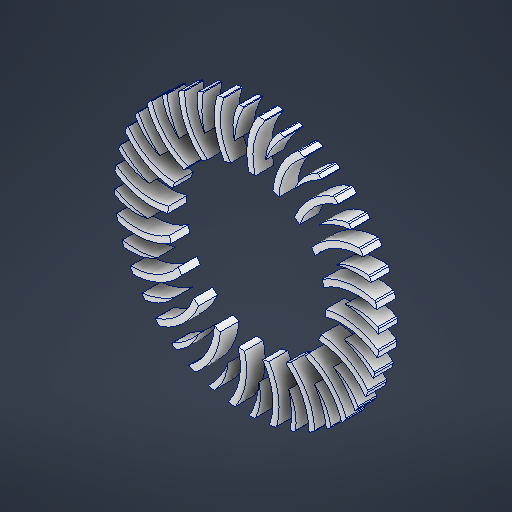
# Autodesk Inventor part: cooling fins
Saved by Autodesk Inventor 2027 (Build 310192060, 192F)
## iProperties
Created: 2026-06-30
Part Number: cooling fins
Material: Aluminum 6061
Document SubType Name: Modeling
Designer: ElieH
Density: 2.7 g/cm^3
Appearance: Aluminum - Flat
Author: ElieH
Autodesk Inventor part; units mm, degrees
ref_plane "YZ Plane" through (0, 0, 0) normal (1, 0, 0) x (0, 1, 0)
ref_plane "XZ Plane" through (0, 0, 0) normal (0, 1, 0) x (-1, 0, 0)
ref_plane "XY Plane" through (0, 0, 0) normal (0, 0, 1) x (1, 0, 0)
sketch "Sketch1" plane through (0, 0, 0) normal (0, 0, 1) x (1, 0, 0)
  circle A0 centre (-0.4718, -0.0423) radius 145.0085
  arc A1 (97.2121, 102.2714) -> (93.1342, 105.9987) centre (0.1506, 0.1757) ccw
  arc A2 (93.1342, 105.9987) -> (91.3573, 106.326) centre (91.9719, 104.6759) ccw
  arc A3 (91.3573, 106.326) -> (84.0675, 103.1281) centre (115.8041, 40.6903) ccw
  arc A4 (91.3573, 106.326) -> (50.7902, 66.7457) centre (115.8041, 40.6903) ccw
  arc A5 (79.6447, 115.6743) -> (50.85, 92.7581) centre (115.8041, 40.6903) ccw
  arc A6 (74.2845, 118.9255) -> (50.85, 92.7581) centre (97.6239, 74.4463) ccw
  arc A7 (76.0515, 118.8497) -> (74.2845, 118.9255) centre (75.1027, 117.3662) ccw
  arc A8 (79.7021, 116.4341) -> (76.0515, 118.8497) centre (0.1506, 0.1757) ccw
  arc A9 (79.6447, 115.6743) -> (79.7021, 116.4341) centre (79.4535, 116.0708) ccw
  arc A10 (97.4056, 102.0871) -> (97.2121, 102.2714) centre (0.1506, 0.1757) ccw
  arc A11 (97.2305, 101.3477) -> (97.0044, 101.278) centre (115.8041, 40.6903) ccw
  arc A12 (97.2305, 101.3477) -> (97.4056, 102.0871) centre (97.1016, 101.7686) ccw
  arc A13 (97.0044, 101.278) -> (56.1595, 62.2961) centre (115.8041, 40.6903) ccw
  arc A14 (56.1595, 62.2961) -> (50.7902, 66.7457) centre (0.1506, 0.1757) ccw
  arc A15 (33.8626, 136.2038) -> (19.6612, 104.0754) centre (69.8045, 101.1138) ccw
  arc A16 (39.9651, 134.768) -> (19.6612, 104.0754) centre (97.526, 74.6279) ccw
  arc A17 (39.7849, 135.5084) -> (35.5665, 136.6777) centre (0.0527, 0.3573) ccw
  arc A18 (35.5665, 136.6777) -> (33.8626, 136.2038) centre (35.1226, 134.9737) ccw
  arc A19 (39.9651, 134.768) -> (39.7849, 135.5084) centre (39.6607, 135.0861) ccw
  arc A20 (53.9933, 129.4967) -> (27.6426, 79.3177) centre (97.526, 74.6279) ccw
  arc A21 (55.7844, 129.7345) -> (53.9933, 129.4967) centre (55.0877, 128.1173) ccw
  arc A22 (60.8144, 127.4497) -> (55.7844, 129.7345) centre (0.0527, 0.3573) ccw
  arc A23 (61.0554, 127.3343) -> (60.8144, 127.4497) centre (0.0527, 0.3573) ccw
  arc A24 (61.1174, 126.577) -> (61.0554, 127.3343) centre (60.8647, 126.9375) ccw
  arc A25 (61.1174, 126.577) -> (60.9238, 126.4408) centre (97.526, 74.6279) ccw
  arc A26 (60.9238, 126.4408) -> (34.1241, 76.7451) centre (97.526, 74.6279) ccw
  arc A27 (34.1241, 76.7451) -> (27.6426, 79.3177) centre (0.0527, 0.3573) ccw
  arc A28 (-9.9202, 140.1453) -> (-13.4984, 105.201) centre (35.1059, 117.8794) ccw
  arc A29 (-3.6727, 140.6656) -> (-13.4984, 105.201) centre (69.6553, 101.2563) ccw
  arc A30 (-4.0729, 141.3141) -> (-8.4461, 141.1225) centre (-0.0964, 0.4998) ccw
  arc A31 (-8.4461, 141.1225) -> (-9.9202, 140.1453) centre (-8.3418, 139.3648) ccw
  arc A32 (-3.6727, 140.6656) -> (-4.0729, 141.3141) centre (-4.0605, 140.874) ccw
  arc A33 (11.2978, 139.9872) -> (1.743, 84.1214) centre (69.6553, 101.2563) ccw
  arc A34 (12.9277, 140.7668) -> (11.2978, 139.9872) centre (12.7649, 139.0135) ccw
  arc A35 (18.4176, 140.1483) -> (12.9277, 140.7668) centre (-0.0964, 0.4998) ccw
  arc A36 (18.6825, 140.1129) -> (18.4176, 140.1483) centre (-0.0964, 0.4998) ccw
  arc A37 (18.9755, 139.4119) -> (18.6825, 140.1129) centre (18.6238, 139.6766) ccw
  arc A38 (18.9755, 139.4119) -> (18.8335, 139.2225) centre (69.6553, 101.2563) ccw
  arc A39 (18.8335, 139.2225) -> (8.7022, 83.6775) centre (69.6553, 101.2563) ccw
  arc A40 (8.7022, 83.6775) -> (1.743, 84.1214) centre (-0.0964, 0.4998) ccw
  arc A41 (-52.7781, 130.3643) -> (-45.3828, 96.0246) centre (-3.0752, 123.102) ccw
  arc A42 (-46.9972, 132.7897) -> (-45.3828, 96.0246) centre (34.92, 117.9688) ccw
  arc A43 (-47.5782, 133.2828) -> (-51.6782, 131.7492) centre (-0.2823, 0.5893) ccw
  arc A44 (-51.6782, 131.7492) -> (-52.7781, 130.3643) centre (-51.0357, 130.1097) ccw
  arc A45 (-46.9972, 132.7897) -> (-47.5782, 133.2828) centre (-47.4304, 132.8681) ccw
  arc A46 (-32.5498, 136.7707) -> (-24.3734, 80.6865) centre (34.92, 117.9688) ccw
  arc A47 (-31.2405, 138.0158) -> (-32.5498, 136.7707) centre (-30.8535, 136.298) ccw
  arc A48 (-25.8282, 139.124) -> (-31.2405, 138.0158) centre (-0.2823, 0.5893) ccw
  arc A49 (-25.5654, 139.1722) -> (-25.8282, 139.124) centre (-0.2823, 0.5893) ccw
  arc A50 (-25.0701, 138.596) -> (-25.5654, 139.1722) centre (-25.4863, 138.7392) ccw
  arc A51 (-25.0701, 138.596) -> (-25.1466, 138.3721) centre (34.92, 117.9688) ccw
  arc A52 (-25.1466, 138.3721) -> (-17.6176, 82.4149) centre (34.92, 117.9688) ccw
  arc A53 (-17.6176, 82.4149) -> (-24.3734, 80.6865) centre (-0.2823, 0.5893) ccw
  arc A54 (-90.5159, 107.8182) -> (-72.871, 77.4444) centre (-41.0015, 116.2704) ccw
  arc A55 (-85.7675, 111.9113) -> (-72.871, 77.4444) centre (-3.2796, 123.1296) ccw
  arc A56 (-86.4724, 112.2007) -> (-89.8978, 109.4752) centre (-0.4868, 0.6169) ccw
  arc A57 (-89.8978, 109.4752) -> (-90.5159, 107.8182) centre (-88.7802, 108.1145) ccw
  arc A58 (-85.7675, 111.9113) -> (-86.4724, 112.2007) centre (-86.2037, 111.852) ccw
  arc A59 (-73.2573, 120.1619) -> (-48.1502, 69.3494) centre (-3.2796, 123.1296) ccw
  arc A60 (-72.3969, 121.7507) -> (-73.2573, 120.1619) centre (-71.498, 120.2365) ccw
  arc A61 (-67.5919, 124.4772) -> (-72.3969, 121.7507) centre (-0.4868, 0.6169) ccw
  arc A62 (-67.3569, 124.6042) -> (-67.5919, 124.4772) centre (-0.4868, 0.6169) ccw
  arc A63 (-66.7077, 124.2093) -> (-67.3569, 124.6042) centre (-67.1479, 124.2168) ccw
  arc A64 (-66.7077, 124.2093) -> (-66.7113, 123.9727) centre (-3.2796, 123.1296) ccw
  arc A65 (-66.7113, 123.9727) -> (-42.2592, 73.0808) centre (-3.2796, 123.1296) ccw
  arc A66 (-42.2592, 73.0808) -> (-48.1502, 69.3494) centre (-0.4868, 0.6169) ccw
  arc A67 (-119.4396, 74.714) -> (-93.2723, 51.2794) centre (-74.9604, 98.0533) ccw
  arc A68 (-116.1884, 80.0741) -> (-93.2723, 51.2794) centre (-41.2044, 116.2335) ccw
  arc A69 (-116.9482, 80.1315) -> (-119.3638, 76.4809) centre (-0.6898, 0.58) ccw
  arc A70 (-119.3638, 76.4809) -> (-119.4396, 74.714) centre (-117.8803, 75.5321) ccw
  arc A71 (-116.1884, 80.0741) -> (-116.9482, 80.1315) centre (-116.5849, 79.8829) ccw
  arc A72 (-106.8401, 91.7867) -> (-67.2598, 51.2196) centre (-41.2044, 116.2335) ccw
  arc A73 (-106.5128, 93.5636) -> (-106.8401, 91.7867) centre (-105.19, 92.4014) ccw
  arc A74 (-102.7855, 97.6415) -> (-106.5128, 93.5636) centre (-0.6898, 0.58) ccw
  arc A75 (-102.6012, 97.835) -> (-102.7855, 97.6415) centre (-0.6898, 0.58) ccw
  arc A76 (-101.8618, 97.6599) -> (-102.6012, 97.835) centre (-102.2827, 97.531) ccw
  arc A77 (-101.8618, 97.6599) -> (-101.7921, 97.4338) centre (-41.2044, 116.2335) ccw
  arc A78 (-101.7921, 97.4338) -> (-62.8102, 56.5889) centre (-41.2044, 116.2335) ccw
  arc A79 (-62.8102, 56.5889) -> (-67.2598, 51.2196) centre (-0.6898, 0.58) ccw
  arc A80 (-136.7179, 34.292) -> (-104.5896, 20.0906) centre (-101.6279, 70.2339) ccw
  arc A81 (-135.2822, 40.3945) -> (-104.5896, 20.0906) centre (-75.142, 97.9555) ccw
  arc A82 (-136.0225, 40.2143) -> (-137.1918, 35.9959) centre (-0.8714, 0.4821) ccw
  arc A83 (-137.1918, 35.9959) -> (-136.7179, 34.292) centre (-135.4878, 35.552) ccw
  arc A84 (-135.2822, 40.3945) -> (-136.0225, 40.2143) centre (-135.6002, 40.0901) ccw
  arc A85 (-130.0108, 54.4227) -> (-79.8318, 28.072) centre (-75.142, 97.9555) ccw
  arc A86 (-130.2486, 56.2138) -> (-130.0108, 54.4227) centre (-128.6314, 55.5171) ccw
  arc A87 (-127.9638, 61.2438) -> (-130.2486, 56.2138) centre (-0.8714, 0.4821) ccw
  arc A88 (-127.8484, 61.4848) -> (-127.9638, 61.2438) centre (-0.8714, 0.4821) ccw
  arc A89 (-127.0911, 61.5468) -> (-127.8484, 61.4848) centre (-127.4516, 61.2941) ccw
  arc A90 (-127.0911, 61.5468) -> (-126.9549, 61.3533) centre (-75.142, 97.9555) ccw
  arc A91 (-126.9549, 61.3533) -> (-77.2592, 34.5535) centre (-75.142, 97.9555) ccw
  arc A92 (-77.2592, 34.5535) -> (-79.8318, 28.072) centre (-0.8714, 0.4821) ccw
  arc A93 (-140.6594, -9.4908) -> (-105.7151, -13.069) centre (-118.3935, 35.5354) ccw
  arc A94 (-141.1797, -3.2433) -> (-105.7151, -13.069) centre (-101.7704, 70.0847) ccw
  arc A95 (-141.8282, -3.6435) -> (-141.6367, -8.0167) centre (-1.0139, 0.333) ccw
  arc A96 (-141.6367, -8.0167) -> (-140.6594, -9.4908) centre (-139.8789, -7.9123) ccw
  arc A97 (-141.1797, -3.2433) -> (-141.8282, -3.6435) centre (-141.3881, -3.6311) ccw
  arc A98 (-140.5013, 11.7272) -> (-84.6355, 2.1724) centre (-101.7704, 70.0847) ccw
  arc A99 (-141.281, 13.3572) -> (-140.5013, 11.7272) centre (-139.5276, 13.1944) ccw
  arc A100 (-140.6624, 18.847) -> (-141.281, 13.3572) centre (-1.0139, 0.333) ccw
  arc A101 (-140.627, 19.1119) -> (-140.6624, 18.847) centre (-1.0139, 0.333) ccw
  arc A102 (-139.926, 19.4049) -> (-140.627, 19.1119) centre (-140.1907, 19.0532) ccw
  arc A103 (-139.926, 19.4049) -> (-139.7366, 19.2629) centre (-101.7704, 70.0847) ccw
  arc A104 (-139.7366, 19.2629) -> (-84.1916, 9.1316) centre (-101.7704, 70.0847) ccw
  arc A105 (-84.1916, 9.1316) -> (-84.6355, 2.1724) centre (-1.0139, 0.333) ccw
  arc A106 (-130.8784, -52.3487) -> (-96.5387, -44.9534) centre (-123.6161, -2.6458) ccw
  arc A107 (-133.3038, -46.5678) -> (-96.5387, -44.9534) centre (-118.483, 35.3494) ccw
  arc A108 (-133.7969, -47.1488) -> (-132.2633, -51.2488) centre (-1.1034, 0.1471) ccw
  arc A109 (-132.2633, -51.2488) -> (-130.8784, -52.3487) centre (-130.6238, -50.6063) ccw
  arc A110 (-133.3038, -46.5678) -> (-133.7969, -47.1488) centre (-133.3822, -47.001) ccw
  arc A111 (-137.2848, -32.1204) -> (-81.2006, -23.944) centre (-118.483, 35.3494) ccw
  arc A112 (-138.5299, -30.8111) -> (-137.2848, -32.1204) centre (-136.8121, -30.4241) ccw
  arc A113 (-139.6381, -25.3988) -> (-138.5299, -30.8111) centre (-1.1034, 0.1471) ccw
  arc A114 (-139.6863, -25.1359) -> (-139.6381, -25.3988) centre (-1.1034, 0.1471) ccw
  arc A115 (-139.1101, -24.6406) -> (-139.6863, -25.1359) centre (-139.2533, -25.0569) ccw
  arc A116 (-139.1101, -24.6406) -> (-138.8862, -24.7172) centre (-118.483, 35.3494) ccw
  arc A117 (-138.8862, -24.7172) -> (-82.929, -17.1882) centre (-118.483, 35.3494) ccw
  arc A118 (-82.929, -17.1882) -> (-81.2006, -23.944) centre (-1.1034, 0.1471) ccw
  arc A119 (-108.3323, -90.0865) -> (-77.9585, -72.4416) centre (-116.7845, -40.572) ccw
  arc A120 (-112.4254, -85.3381) -> (-77.9585, -72.4416) centre (-123.6437, -2.8502) ccw
  arc A121 (-112.7148, -86.043) -> (-109.9893, -89.4684) centre (-1.131, -0.0574) ccw
  arc A122 (-109.9893, -89.4684) -> (-108.3323, -90.0865) centre (-108.6286, -88.3508) ccw
  arc A123 (-112.4254, -85.3381) -> (-112.7148, -86.043) centre (-112.3661, -85.7743) ccw
  arc A124 (-120.676, -72.8279) -> (-69.8635, -47.7208) centre (-123.6437, -2.8502) ccw
  arc A125 (-122.2648, -71.9675) -> (-120.676, -72.8279) centre (-120.7506, -71.0686) ccw
  arc A126 (-124.9913, -67.1625) -> (-122.2648, -71.9675) centre (-1.131, -0.0574) ccw
  arc A127 (-125.1183, -66.9275) -> (-124.9913, -67.1625) centre (-1.131, -0.0574) ccw
  arc A128 (-124.7234, -66.2783) -> (-125.1183, -66.9275) centre (-124.7309, -66.7185) ccw
  arc A129 (-124.7234, -66.2783) -> (-124.4868, -66.2819) centre (-123.6437, -2.8502) ccw
  arc A130 (-124.4868, -66.2819) -> (-73.5949, -41.8298) centre (-123.6437, -2.8502) ccw
  arc A131 (-73.5949, -41.8298) -> (-69.8635, -47.7208) centre (-1.131, -0.0574) ccw
  arc A132 (-75.2281, -119.0102) -> (-51.7935, -92.8428) centre (-98.5674, -74.531) ccw
  arc A133 (-80.5882, -115.759) -> (-51.7935, -92.8428) centre (-116.7476, -40.775) ccw
  arc A134 (-80.6456, -116.5188) -> (-76.995, -118.9344) centre (-1.0941, -0.2604) ccw
  arc A135 (-76.995, -118.9344) -> (-75.2281, -119.0102) centre (-76.0462, -117.4509) ccw
  arc A136 (-80.5882, -115.759) -> (-80.6456, -116.5188) centre (-80.397, -116.1555) ccw
  arc A137 (-92.3008, -106.4107) -> (-51.7337, -66.8304) centre (-116.7476, -40.775) ccw
  arc A138 (-94.0778, -106.0833) -> (-92.3008, -106.4107) centre (-92.9155, -104.7606) ccw
  arc A139 (-98.1556, -102.3561) -> (-94.0778, -106.0833) centre (-1.0941, -0.2604) ccw
  arc A140 (-98.3491, -102.1718) -> (-98.1556, -102.3561) centre (-1.0941, -0.2604) ccw
  arc A141 (-98.174, -101.4324) -> (-98.3491, -102.1718) centre (-98.0451, -101.8533) ccw
  arc A142 (-98.174, -101.4324) -> (-97.9479, -101.3627) centre (-116.7476, -40.775) ccw
  arc A143 (-97.9479, -101.3627) -> (-57.103, -62.3808) centre (-116.7476, -40.775) ccw
  arc A144 (-57.103, -62.3808) -> (-51.7337, -66.8304) centre (-1.0941, -0.2604) ccw
  arc A145 (-34.8061, -136.2885) -> (-20.6047, -104.1601) centre (-70.748, -101.1985) ccw
  arc A146 (-40.9086, -134.8527) -> (-20.6047, -104.1601) centre (-98.4696, -74.7126) ccw
  arc A147 (-40.7284, -135.5931) -> (-36.51, -136.7624) centre (-0.9963, -0.442) ccw
  arc A148 (-36.51, -136.7624) -> (-34.8061, -136.2885) centre (-36.0661, -135.0583) ccw
  arc A149 (-40.9086, -134.8527) -> (-40.7284, -135.5931) centre (-40.6042, -135.1708) ccw
  arc A150 (-54.9368, -129.5814) -> (-28.5862, -79.4024) centre (-98.4696, -74.7126) ccw
  arc A151 (-56.7279, -129.8192) -> (-54.9368, -129.5814) centre (-56.0312, -128.202) ccw
  arc A152 (-61.7579, -127.5344) -> (-56.7279, -129.8192) centre (-0.9963, -0.442) ccw
  arc A153 (-61.9989, -127.419) -> (-61.7579, -127.5344) centre (-0.9963, -0.442) ccw
  arc A154 (-62.0609, -126.6617) -> (-61.9989, -127.419) centre (-61.8083, -127.0222) ccw
  arc A155 (-62.0609, -126.6617) -> (-61.8674, -126.5255) centre (-98.4696, -74.7126) ccw
  arc A156 (-61.8674, -126.5255) -> (-35.0676, -76.8298) centre (-98.4696, -74.7126) ccw
  arc A157 (-35.0676, -76.8298) -> (-28.5862, -79.4024) centre (-0.9963, -0.442) ccw
  arc A158 (8.9767, -140.23) -> (12.5549, -105.2857) centre (-36.0495, -117.9641) ccw
  arc A159 (2.7292, -140.7503) -> (12.5549, -105.2857) centre (-70.5988, -101.341) ccw
  arc A160 (3.1294, -141.3988) -> (7.5026, -141.2072) centre (-0.8471, -0.5845) ccw
  arc A161 (7.5026, -141.2072) -> (8.9767, -140.23) centre (7.3982, -139.4495) ccw
  arc A162 (2.7292, -140.7503) -> (3.1294, -141.3988) centre (3.117, -140.9587) ccw
  arc A163 (-12.2413, -140.0719) -> (-2.6865, -84.2061) centre (-70.5988, -101.341) ccw
  arc A164 (-13.8713, -140.8515) -> (-12.2413, -140.0719) centre (-13.7085, -139.0982) ccw
  arc A165 (-19.3611, -140.233) -> (-13.8713, -140.8515) centre (-0.8471, -0.5845) ccw
  arc A166 (-19.626, -140.1976) -> (-19.3611, -140.233) centre (-0.8471, -0.5845) ccw
  arc A167 (-19.919, -139.4966) -> (-19.626, -140.1976) centre (-19.5673, -139.7613) ccw
  arc A168 (-19.919, -139.4966) -> (-19.777, -139.3072) centre (-70.5988, -101.341) ccw
  arc A169 (-19.777, -139.3072) -> (-9.6457, -83.7622) centre (-70.5988, -101.341) ccw
  arc A170 (-9.6457, -83.7622) -> (-2.6865, -84.2061) centre (-0.8471, -0.5845) ccw
  arc A171 (51.8346, -130.449) -> (44.4393, -96.1092) centre (2.1317, -123.1867) ccw
  arc A172 (46.0537, -132.8744) -> (44.4393, -96.1092) centre (-35.8636, -118.0535) ccw
  arc A173 (46.6347, -133.3675) -> (50.7347, -131.8339) centre (-0.6612, -0.674) ccw
  arc A174 (50.7347, -131.8339) -> (51.8346, -130.449) centre (50.0922, -130.1944) ccw
  arc A175 (46.0537, -132.8744) -> (46.6347, -133.3675) centre (46.4869, -132.9528) ccw
  arc A176 (31.6063, -136.8554) -> (23.4299, -80.7712) centre (-35.8636, -118.0535) ccw
  arc A177 (30.297, -138.1005) -> (31.6063, -136.8554) centre (29.91, -136.3827) ccw
  arc A178 (24.8847, -139.2087) -> (30.297, -138.1005) centre (-0.6612, -0.674) ccw
  arc A179 (24.6218, -139.2569) -> (24.8847, -139.2087) centre (-0.6612, -0.674) ccw
  arc A180 (24.1265, -138.6807) -> (24.6218, -139.2569) centre (24.5428, -138.8239) ccw
  arc A181 (24.1265, -138.6807) -> (24.2031, -138.4568) centre (-35.8636, -118.0535) ccw
  arc A182 (24.2031, -138.4568) -> (16.6741, -82.4996) centre (-35.8636, -118.0535) ccw
  arc A183 (16.6741, -82.4996) -> (23.4299, -80.7712) centre (-0.6612, -0.674) ccw
  arc A184 (89.5724, -107.9029) -> (71.9275, -77.5291) centre (40.0579, -116.3551) ccw
  arc A185 (84.824, -111.996) -> (71.9275, -77.5291) centre (2.3361, -123.2143) ccw
  arc A186 (85.5289, -112.2854) -> (88.9543, -109.5599) centre (-0.4567, -0.7016) ccw
  arc A187 (88.9543, -109.5599) -> (89.5724, -107.9029) centre (87.8366, -108.1992) ccw
  arc A188 (84.824, -111.996) -> (85.5289, -112.2854) centre (85.2602, -111.9367) ccw
  arc A189 (72.3138, -120.2466) -> (47.2067, -69.434) centre (2.3361, -123.2143) ccw
  arc A190 (71.4534, -121.8354) -> (72.3138, -120.2466) centre (70.5545, -120.3212) ccw
  arc A191 (66.6484, -124.5619) -> (71.4534, -121.8354) centre (-0.4567, -0.7016) ccw
  arc A192 (66.4133, -124.6889) -> (66.6484, -124.5619) centre (-0.4567, -0.7016) ccw
  arc A193 (65.7642, -124.294) -> (66.4133, -124.6889) centre (66.2044, -124.3015) ccw
  arc A194 (65.7642, -124.294) -> (65.7678, -124.0573) centre (2.3361, -123.2143) ccw
  arc A195 (65.7678, -124.0573) -> (41.3156, -73.1655) centre (2.3361, -123.2143) ccw
  arc A196 (41.3156, -73.1655) -> (47.2067, -69.434) centre (-0.4567, -0.7016) ccw
  arc A197 (118.4961, -74.7987) -> (92.3287, -51.3641) centre (74.0169, -98.138) ccw
  arc A198 (115.2449, -80.1588) -> (92.3287, -51.3641) centre (40.2609, -116.3182) ccw
  arc A199 (116.0047, -80.2162) -> (118.4203, -76.5656) centre (-0.2538, -0.6647) ccw
  arc A200 (118.4203, -76.5656) -> (118.4961, -74.7987) centre (116.9368, -75.6168) ccw
  arc A201 (115.2449, -80.1588) -> (116.0047, -80.2162) centre (115.6414, -79.9676) ccw
  arc A202 (105.8966, -91.8714) -> (66.3163, -51.3043) centre (40.2609, -116.3182) ccw
  arc A203 (105.5692, -93.6483) -> (105.8966, -91.8714) centre (104.2465, -92.486) ccw
  arc A204 (101.842, -97.7262) -> (105.5692, -93.6483) centre (-0.2538, -0.6647) ccw
  arc A205 (101.6577, -97.9197) -> (101.842, -97.7262) centre (-0.2538, -0.6647) ccw
  arc A206 (100.9183, -97.7446) -> (101.6577, -97.9197) centre (101.3392, -97.6157) ccw
  arc A207 (100.9183, -97.7446) -> (100.8486, -97.5185) centre (40.2609, -116.3182) ccw
  arc A208 (100.8486, -97.5185) -> (61.8667, -56.6736) centre (40.2609, -116.3182) ccw
  arc A209 (61.8667, -56.6736) -> (66.3163, -51.3043) centre (-0.2538, -0.6647) ccw
  arc A210 (135.7744, -34.3767) -> (103.646, -20.1753) centre (100.6844, -70.3186) ccw
  arc A211 (134.3386, -40.4792) -> (103.646, -20.1753) centre (74.1985, -98.0402) ccw
  arc A212 (135.079, -40.299) -> (136.2482, -36.0806) centre (-0.0721, -0.5668) ccw
  arc A213 (136.2482, -36.0806) -> (135.7744, -34.3767) centre (134.5442, -35.6367) ccw
  arc A214 (134.3386, -40.4792) -> (135.079, -40.299) centre (134.6567, -40.1748) ccw
  arc A215 (129.0673, -54.5074) -> (78.8883, -28.1567) centre (74.1985, -98.0402) ccw
  arc A216 (129.3051, -56.2985) -> (129.0673, -54.5074) centre (127.6879, -55.6018) ccw
  arc A217 (127.0203, -61.3285) -> (129.3051, -56.2985) centre (-0.0721, -0.5668) ccw
  arc A218 (126.9048, -61.5695) -> (127.0203, -61.3285) centre (-0.0721, -0.5668) ccw
  arc A219 (126.1475, -61.6315) -> (126.9048, -61.5695) centre (126.508, -61.3788) ccw
  arc A220 (126.1475, -61.6315) -> (126.0114, -61.438) centre (74.1985, -98.0402) ccw
  arc A221 (126.0114, -61.438) -> (76.3157, -34.6382) centre (74.1985, -98.0402) ccw
  arc A222 (76.3157, -34.6382) -> (78.8883, -28.1567) centre (-0.0721, -0.5668) ccw
  arc A223 (139.7159, 9.4061) -> (104.7716, 12.9843) centre (117.45, -35.6201) ccw
  arc A224 (140.2362, 3.1586) -> (104.7716, 12.9843) centre (100.8269, -70.1694) ccw
  arc A225 (140.8847, 3.5588) -> (140.6931, 7.932) centre (0.0704, -0.4177) ccw
  arc A226 (140.6931, 7.932) -> (139.7159, 9.4061) centre (138.9354, 7.8276) ccw
  arc A227 (140.2362, 3.1586) -> (140.8847, 3.5588) centre (140.4446, 3.5464) ccw
  arc A228 (139.5578, -11.8119) -> (83.692, -2.2571) centre (100.8269, -70.1694) ccw
  arc A229 (140.3374, -13.4419) -> (139.5578, -11.8119) centre (138.5841, -13.2791) ccw
  arc A230 (139.7189, -18.9317) -> (140.3374, -13.4419) centre (0.0704, -0.4177) ccw
  arc A231 (139.6835, -19.1966) -> (139.7189, -18.9317) centre (0.0704, -0.4177) ccw
  arc A232 (138.9825, -19.4896) -> (139.6835, -19.1966) centre (139.2472, -19.1379) ccw
  arc A233 (138.9825, -19.4896) -> (138.7931, -19.3476) centre (100.8269, -70.1694) ccw
  arc A234 (138.7931, -19.3476) -> (83.2481, -9.2163) centre (100.8269, -70.1694) ccw
  arc A235 (83.2481, -9.2163) -> (83.692, -2.2571) centre (0.0704, -0.4177) ccw
  arc A236 (129.9349, 52.264) -> (95.5951, 44.8687) centre (122.6726, 2.5611) ccw
  arc A237 (132.3603, 46.4831) -> (95.5951, 44.8687) centre (117.5394, -35.4341) ccw
  arc A238 (132.8534, 47.0641) -> (131.3198, 51.1641) centre (0.1599, -0.2318) ccw
  arc A239 (131.3198, 51.1641) -> (129.9349, 52.264) centre (129.6803, 50.5216) ccw
  arc A240 (132.3603, 46.4831) -> (132.8534, 47.0641) centre (132.4387, 46.9163) ccw
  arc A241 (136.3413, 32.0357) -> (80.2571, 23.8593) centre (117.5394, -35.4341) ccw
  arc A242 (137.5864, 30.7264) -> (136.3413, 32.0357) centre (135.8686, 30.3394) ccw
  arc A243 (138.6946, 25.3141) -> (137.5864, 30.7264) centre (0.1599, -0.2318) ccw
  arc A244 (138.7428, 25.0513) -> (138.6946, 25.3141) centre (0.1599, -0.2318) ccw
  arc A245 (138.1666, 24.5559) -> (138.7428, 25.0513) centre (138.3097, 24.9722) ccw
  arc A246 (138.1666, 24.5559) -> (137.9427, 24.6325) centre (117.5394, -35.4341) ccw
  arc A247 (137.9427, 24.6325) -> (81.9855, 17.1035) centre (117.5394, -35.4341) ccw
  arc A248 (81.9855, 17.1035) -> (80.2571, 23.8593) centre (0.1599, -0.2318) ccw
  arc A249 (107.3888, 90.0018) -> (77.015, 72.3569) centre (115.841, 40.4874) ccw
  arc A250 (111.4819, 85.2534) -> (77.015, 72.3569) centre (122.7002, 2.7655) ccw
  arc A251 (111.7713, 85.9583) -> (109.0458, 89.3837) centre (0.1875, -0.0273) ccw
  arc A252 (109.0458, 89.3837) -> (107.3888, 90.0018) centre (107.6851, 88.2661) ccw
  arc A253 (111.4819, 85.2534) -> (111.7713, 85.9583) centre (111.4226, 85.6896) ccw
  arc A254 (119.7325, 72.7432) -> (68.9199, 47.6361) centre (122.7002, 2.7655) ccw
  arc A255 (121.3213, 71.8828) -> (119.7325, 72.7432) centre (119.8071, 70.9839) ccw
  arc A256 (124.0478, 67.0778) -> (121.3213, 71.8828) centre (0.1875, -0.0273) ccw
  arc A257 (124.1748, 66.8428) -> (124.0478, 67.0778) centre (0.1875, -0.0273) ccw
  arc A258 (123.7799, 66.1936) -> (124.1748, 66.8428) centre (123.7874, 66.6338) ccw
  arc A259 (123.7799, 66.1936) -> (123.5432, 66.1972) centre (122.7002, 2.7655) ccw
  arc A260 (123.5432, 66.1972) -> (72.6514, 41.7451) centre (122.7002, 2.7655) ccw
  arc A261 (72.6514, 41.7451) -> (68.9199, 47.6361) centre (0.1875, -0.0273) ccw
  point P0 (93.1342, 105.9987)
  point P1 (84.0675, 103.1281)
  point P2 (50.7902, 66.7457)
  point P3 (56.1595, 62.2961)
  point P4 (97.2305, 101.3477)
  point P5 (97.4056, 102.0871)
  point P6 (79.6447, 115.6743)
  point P7 (79.7021, 116.4341)
  point P8 (76.0515, 118.8497)
  point P9 (74.2845, 118.9255)
  point P10 (50.85, 92.7581)
  point P11 (-141.1797, -3.2433)
  point P12 (-141.8282, -3.6435)
  point P13 (-141.6367, -8.0167)
  point P14 (-140.6594, -9.4908)
  point P15 (-105.7151, -13.069)
  point P16 (-139.926, 19.4049)
  point P17 (-140.627, 19.1119)
  point P18 (-141.281, 13.3572)
  point P19 (-84.6355, 2.1724)
  point P20 (-84.1916, 9.1316)
  point P21 (-135.2822, 40.3945)
  point P22 (-136.0225, 40.2143)
  point P23 (-137.1918, 35.9959)
  point P24 (-136.7179, 34.292)
  point P25 (-104.5896, 20.0906)
  point P26 (-127.0911, 61.5468)
  point P27 (-127.8484, 61.4848)
  point P28 (-130.2486, 56.2138)
  point P29 (-79.8318, 28.072)
  point P30 (-77.2592, 34.5535)
  point P31 (-139.1101, -24.6406)
  point P32 (-139.6863, -25.1359)
  point P33 (-138.5299, -30.8111)
  point P34 (-81.2006, -23.944)
  point P35 (-82.929, -17.1882)
  point P36 (-133.3038, -46.5678)
  point P37 (-133.7969, -47.1488)
  point P38 (-132.2633, -51.2488)
  point P39 (-130.8784, -52.3487)
  point P40 (-96.5387, -44.9534)
  point P41 (-124.7234, -66.2783)
  point P42 (-125.1183, -66.9275)
  point P43 (-122.2648, -71.9675)
  point P44 (-69.8635, -47.7208)
  point P45 (-73.5949, -41.8298)
  point P46 (-112.4254, -85.3381)
  point P47 (-112.7148, -86.043)
  point P48 (-109.9893, -89.4684)
  point P49 (-108.3323, -90.0865)
  point P50 (-77.9585, -72.4416)
  point P51 (-98.174, -101.4324)
  point P52 (-98.3491, -102.1718)
  point P53 (-94.0778, -106.0833)
  point P54 (-51.7337, -66.8304)
  point P55 (-57.103, -62.3808)
  point P56 (-80.5882, -115.759)
  point P57 (-80.6456, -116.5188)
  point P58 (-76.995, -118.9344)
  point P59 (-75.2281, -119.0102)
  point P60 (-51.7935, -92.8428)
  point P61 (-62.0609, -126.6617)
  point P62 (-61.9989, -127.419)
  point P63 (-56.7279, -129.8192)
  point P64 (-28.5862, -79.4024)
  point P65 (-35.0676, -76.8298)
  point P66 (-40.9086, -134.8527)
  point P67 (-40.7284, -135.5931)
  point P68 (-36.51, -136.7624)
  point P69 (-34.8061, -136.2885)
  point P70 (-20.6047, -104.1601)
  point P71 (-19.919, -139.4966)
  point P72 (-19.626, -140.1976)
  point P73 (-13.8713, -140.8515)
  point P74 (-2.6865, -84.2061)
  point P75 (-9.6457, -83.7622)
  point P76 (2.7292, -140.7503)
  point P77 (3.1294, -141.3988)
  point P78 (7.5026, -141.2072)
  point P79 (8.9767, -140.23)
  point P80 (12.5549, -105.2857)
  point P81 (24.1265, -138.6807)
  point P82 (24.6218, -139.2569)
  point P83 (30.297, -138.1005)
  point P84 (23.4299, -80.7712)
  point P85 (16.6741, -82.4996)
  point P86 (46.0537, -132.8744)
  point P87 (46.6347, -133.3675)
  point P88 (50.7347, -131.8339)
  point P89 (51.8346, -130.449)
  point P90 (44.4393, -96.1092)
  point P91 (65.7642, -124.294)
  point P92 (66.4133, -124.6889)
  point P93 (71.4534, -121.8354)
  point P94 (47.2067, -69.434)
  point P95 (41.3156, -73.1655)
  point P96 (84.824, -111.996)
  point P97 (85.5289, -112.2854)
  point P98 (88.9543, -109.5599)
  point P99 (89.5724, -107.9029)
  point P100 (71.9275, -77.5291)
  point P101 (100.9183, -97.7446)
  point P102 (101.6577, -97.9197)
  point P103 (105.5692, -93.6483)
  point P104 (66.3163, -51.3043)
  point P105 (61.8667, -56.6736)
  point P106 (115.2449, -80.1588)
  point P107 (116.0047, -80.2162)
  point P108 (118.4203, -76.5656)
  point P109 (118.4961, -74.7987)
  point P110 (92.3287, -51.3641)
  point P111 (126.1475, -61.6315)
  point P112 (126.9048, -61.5695)
  point P113 (129.3051, -56.2985)
  point P114 (78.8883, -28.1567)
  point P115 (76.3157, -34.6382)
  point P116 (134.3386, -40.4792)
  point P117 (135.079, -40.299)
  point P118 (136.2482, -36.0806)
  point P119 (135.7744, -34.3767)
  point P120 (103.646, -20.1753)
  point P121 (138.9825, -19.4896)
  point P122 (139.6835, -19.1966)
  point P123 (140.3374, -13.4419)
  point P124 (83.692, -2.2571)
  point P125 (83.2481, -9.2163)
  point P126 (140.2362, 3.1586)
  point P127 (140.8847, 3.5588)
  point P128 (140.6931, 7.932)
  point P129 (139.7159, 9.4061)
  point P130 (104.7716, 12.9843)
  point P131 (138.1666, 24.5559)
  point P132 (138.7428, 25.0513)
  point P133 (137.5864, 30.7264)
  point P134 (80.2571, 23.8593)
  point P135 (81.9855, 17.1035)
  point P136 (132.3603, 46.4831)
  point P137 (132.8534, 47.0641)
  point P138 (131.3198, 51.1641)
  point P139 (129.9349, 52.264)
  point P140 (95.5951, 44.8687)
  point P141 (123.7799, 66.1936)
  point P142 (124.1748, 66.8428)
  point P143 (121.3213, 71.8828)
  point P144 (68.9199, 47.6361)
  point P145 (72.6514, 41.7451)
  point P146 (111.4819, 85.2534)
  point P147 (111.7713, 85.9583)
  point P148 (109.0458, 89.3837)
  point P149 (107.3888, 90.0018)
  point P150 (77.015, 72.3569)
  point P151 (61.1174, 126.577)
  point P152 (61.0554, 127.3343)
  point P153 (55.7844, 129.7345)
  point P154 (27.6426, 79.3177)
  point P155 (34.1241, 76.7451)
  point P156 (39.9651, 134.768)
  point P157 (39.7849, 135.5084)
  point P158 (35.5665, 136.6777)
  point P159 (33.8626, 136.2038)
  point P160 (19.6612, 104.0754)
  point P161 (18.9755, 139.4119)
  point P162 (18.6825, 140.1129)
  point P163 (12.9277, 140.7668)
  point P164 (1.743, 84.1214)
  point P165 (8.7022, 83.6775)
  point P166 (-3.6727, 140.6656)
  point P167 (-4.0729, 141.3141)
  point P168 (-8.4461, 141.1225)
  point P169 (-9.9202, 140.1453)
  point P170 (-13.4984, 105.201)
  point P171 (-25.0701, 138.596)
  point P172 (-25.5654, 139.1722)
  point P173 (-31.2405, 138.0158)
  point P174 (-24.3734, 80.6865)
  point P175 (-17.6176, 82.4149)
  point P176 (-46.9972, 132.7897)
  point P177 (-47.5782, 133.2828)
  point P178 (-51.6782, 131.7492)
  point P179 (-52.7781, 130.3643)
  point P180 (-45.3828, 96.0246)
  point P181 (-116.1884, 80.0741)
  point P182 (-116.9482, 80.1315)
  point P183 (-119.3638, 76.4809)
  point P184 (-119.4396, 74.714)
  point P185 (-93.2723, 51.2794)
  point P186 (-101.8618, 97.6599)
  point P187 (-102.6012, 97.835)
  point P188 (-106.5128, 93.5636)
  point P189 (-67.2598, 51.2196)
  point P190 (-62.8102, 56.5889)
  point P191 (-85.7675, 111.9113)
  point P192 (-86.4724, 112.2007)
  point P193 (-89.8978, 109.4752)
  point P194 (-90.5159, 107.8182)
  point P195 (-72.871, 77.4444)
  point P196 (-66.7077, 124.2093)
  point P197 (-67.3569, 124.6042)
  point P198 (-72.3969, 121.7507)
  point P199 (-48.1502, 69.3494)
  dimension "d43" = 360
  constraints: 522 point on circle, 262 centre point, 981 other
extrude "Extrusion6" add sketch "Sketch1" along normal blind 20 contours A10 A12 A11 A13 A14 A4 A3 A2 A1 | A5 A6 A7 A8 A9 | A18 A17 A19 A16 A15 | A21 A22 A23 A24 A25 A26 A27 A20 | A31 A30 A32 A29 A28 | A34 A35 A36 A37 A38 A39 A40 A33 | A44 A43 A45 A42 A41 | A47 A48 A49 A50 A51 A52 A53 A46 | A57 A56 A58 A55 A54 | A60 A61 A62 A63 A64 A65 A66 A59 | A70 A69 A71 A68 A67 | A73 A74 A75 A76 A77 A78 A79 A72 | A83 A82 A84 A81 A80 | A86 A87 A88 A89 A90 A91 A92 A85 | A96 A95 A97 A94 A93 | A99 A100 A101 A102 A103 A104 A105 A98 | A109 A108 A110 A107 A106 | A112 A113 A114 A115 A116 A117 A118 A111 | A122 A121 A123 A120 A119 | A125 A126 A127 A128 A129 A130 A131 A124 | A135 A134 A136 A133 A132 | A138 A139 A140 A141 A142 A143 A144 A137 | A148 A147 A149 A146 A145 | A151 A152 A153 A154 A155 A156 A157 A150 | A161 A160 A162 A159 A158 | A164 A165 A166 A167 A168 A169 A170 A163 | A174 A173 A175 A172 A171 | A177 A178 A179 A180 A181 A182 A183 A176 | A187 A186 A188 A185 A184 | A190 A191 A192 A193 A194 A195 A196 A189 | A200 A199 A201 A198 A197 | A203 A204 A205 A206 A207 A208 A209 A202 | A213 A212 A214 A211 A210 | A216 A217 A218 A219 A220 A221 A222 A215 | A226 A225 A227 A224 A223 | A229 A230 A231 A232 A233 A234 A235 A228 | A239 A238 A240 A237 A236 | A242 A243 A244 A245 A246 A247 A248 A241 | A252 A251 A253 A250 A249 | A255 A256 A257 A258 A259 A260 A261 A254
body "Solid2"
